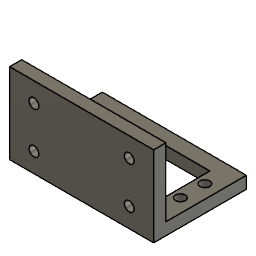
servoholderfinalfinal (Autodesk Fusion 360 design; units mm, degrees)
part number: 2026-04-23-13-37-47-061
Autodesk Fusion 360 part; units mm, degrees
sketch "Sketch1" plane through (0, 0, 0) normal (0, 1, 0) x (1, 0, 0)
  line L0 (0, 0) -> (59, 0)
  line L1 (59, 0) -> (59, 33)
  line L2 (59, 33) -> (0, 33)
  line L3 (0, 33) -> (0, 0)
  line L4 (9, 27) -> (50, 27)
  line L5 (50, 27) -> (50, 6)
  line L6 (50, 6) -> (9, 6)
  line L7 (9, 6) -> (9, 27)
  line L8 (9, 27) -> (50, 27)
  line L9 (50, 27) -> (50, 6)
  line L10 (9, 6) -> (9, 27)
  line L11 (50, 6) -> (9, 6)
  circle A0 centre (53.5, 21.5) radius 2
  circle A1 centre (53.5, 11.5) radius 2
  circle A2 centre (5.5, 21.5) radius 2
  circle A3 centre (5.5, 11.5) radius 2
  dimension "d1" = 59
  dimension "d2" = 33
  dimension "d3" = 41
  dimension "d4" = 21
  dimension "d5" = 41
  dimension "d6" = 21
  dimension "d9" = 4
  dimension "d10" = 10
  dimension "d11" = 4
  dimension "d12" = 48
  dimension "d13" = 4
  dimension "d14" = 10
  dimension "d15" = 4
  constraint horizontal L0
  constraint vertical L1
  constraint horizontal L2
  constraint vertical L3
  constraint coincident L0.start L3.end
  constraint horizontal L4
  constraint vertical L5
  constraint horizontal L6
  constraint vertical L7
  constraint horizontal L8
  constraint vertical L9
  constraint horizontal L11
  constraint vertical L10
  measures "d1" distance of L0.start L0.end
  measures "d2" distance of L0.start L2.end
  measures "d3" distance of L4.start L4.end
  measures "d4" distance of L4.start L6.end
  measures "d5" distance of L4.end L4.start
  measures "d6" distance of L6.end L4.start
  measures "d9" diameter of A0
  measures "d10" distance of A0.centre A1.centre
  measures "d11" diameter of A1
  measures "d12" distance of A0.centre A2.centre
  measures "d13" diameter of A2
  measures "d14" distance of A2.centre A3.centre
  measures "d15" diameter of A3
sketch "Sketch2" plane through (0, 0, 0) normal (0, 1, 0) x (1, 0, 0)
sketch "Sketch3" plane through (0, 0, 0) normal (0, 1, 0) x (1, 0, 0)
sketch "Sketch4" plane through (0, 0, 0) normal (0, 0, 1) x (1, 0, 0)
  line L0 (0, 0) -> (59, 0)
  line L1 (59, 0) -> (59, 33)
  line L2 (59, 33) -> (0, 33)
  line L3 (0, 33) -> (0, 0)
  dimension "d16" = 59
  dimension "d17" = 33
  constraint horizontal L0
  constraint vertical L1
  constraint horizontal L2
  constraint vertical L3
  constraint coincident L0.start L3.end
  measures "d16" distance of L0.start L0.end
  measures "d17" distance of L0.start L2.end
sketch "Sketch5" plane through (0, 0, 0) normal (0, 0, 1) x (1, 0, 0)
  circle A0 centre (10, 25) radius 2
  circle A1 centre (10, 8) radius 2
  circle A2 centre (49, 25) radius 2
  circle A3 centre (49, 8) radius 2
  dimension "d31" = 4
  dimension "d32" = 4
  dimension "d33" = 4
  dimension "d34" = 4
  measures "d31" diameter of A0
  measures "d32" diameter of A1
  measures "d33" diameter of A2
  measures "d34" diameter of A3
extrude "Extrude1" add sketch "Sketch4" along normal blind 5
extrude "Extrude2" add sketch "Sketch1" along normal blind 5
hole "Hole1" at (49, 25, 0) at (10, 25, 0) at (10, 8, 0) at (49, 8, 0) direction (0, 0, 1) diameter 4 depth 5 tip angle 118
